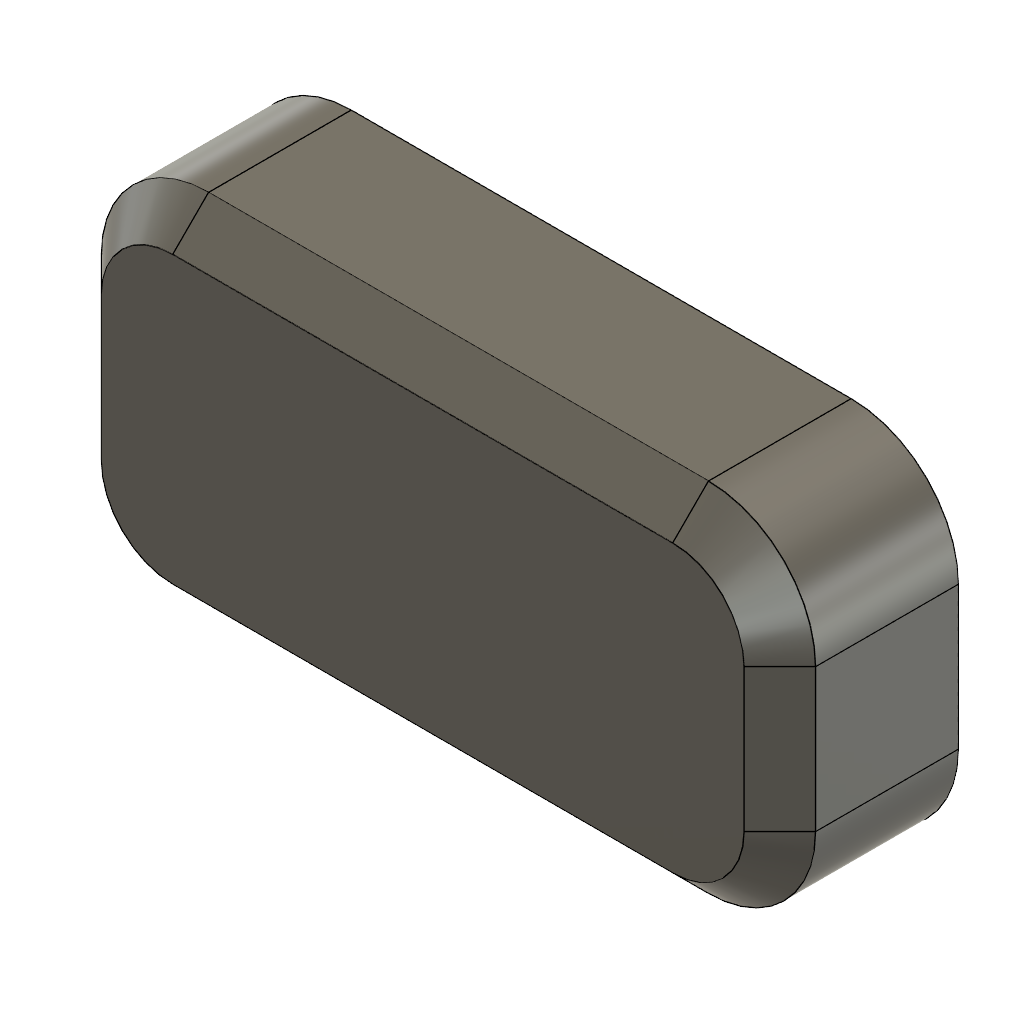
chamfer_tangent_chain (Autodesk Fusion 360 design; units mm, degrees)
part number: 2026-11-12-22-57-15-241
Autodesk Fusion 360 part; units mm, degrees
sketch "Sketch1" plane through (0, 0, 0) normal (0, 0, 1) x (1, 0, 0)
  line L0 (3, 0) -> (17, 0)
  line L1 (20, 3) -> (20, 7)
  line L2 (17, 10) -> (3, 10)
  line L3 (0, 7) -> (0, 3)
  arc A0 (17, 0) -> (20, 3) centre (17, 3) ccw
  arc A1 (20, 7) -> (17, 10) centre (17, 7) ccw
  arc A2 (3, 10) -> (0, 7) centre (3, 7) ccw
  arc A3 (0, 3) -> (3, 0) centre (3, 3) ccw
  constraint tangent L0 A0
  constraint tangent L1 A0
  constraint tangent L1 A1
  constraint tangent L2 A1
  constraint tangent L2 A2
  constraint tangent L3 A2
  constraint tangent L3 A3
  constraint tangent L0 A3
extrude "Extrude1" add sketch "Sketch1" along normal blind 5
chamfer "Chamfer1" distance 1 angle 45 8 edges at (10, 0, 5) (19.1213, 0.8787, 5) (20, 5, 5) (19.1213, 9.1213, 5) (10, 10, 5) (0.8787, 9.1213, 5) (0, 5, 5) (0.8787, 0.8787, 5) tangent chain off
